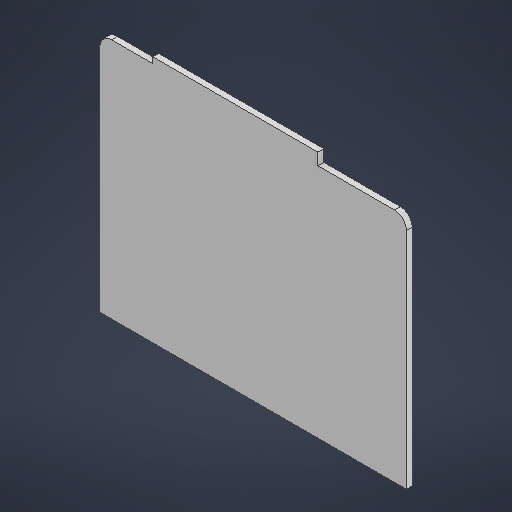
# Autodesk Inventor part: 屏幕pcb
Saved by Autodesk Inventor 2025 (Build 290162000, 162)
## iProperties
Created: 2025-09-15
Part Number: 屏幕pcb
Material: 常规
Document SubType Name: Modeling
Designer: XH
Density: 1 g/cm^3
Appearance: 默认
Author: XH
Autodesk Inventor part; units mm, degrees
ref_plane "YZ Plane" through (0, 0, 0) normal (1, 0, 0) x (0, 1, 0)
ref_plane "XZ Plane" through (0, 0, 0) normal (0, 1, 0) x (-1, 0, 0)
ref_plane "XY Plane" through (0, 0, 0) normal (0, 0, 1) x (1, 0, 0)
sketch "草图1" plane through (0, 0, 0) normal (0, 0, 1) x (1, 0, 0)
  line L0 (26, -21) -> (-26, -21)
  line L1 (-26, -21) -> (-26, 21)
  line L2 (-26, 21) -> (26, 21)
  line L3 (26, 21) -> (26, -21)
  line L4 (26, -21) -> (-26, 21) construction
  line L5 (-26, -21) -> (26, 21) construction
  line L6 (11, 21) -> (26, 21)
  line L7 (26, 21) -> (26, 19)
  line L8 (26, 19) -> (11, 19)
  line L9 (11, 19) -> (11, 21)
  line L10 (-26, 21) -> (-17, 21)
  line L11 (-17, 21) -> (-17, 20)
  line L12 (-17, 20) -> (-26, 20)
  line L13 (-26, 20) -> (-26, 21)
  point P0 (0, 0)
  point P1 (-26, 20.5)
  dimension "d0" = 42
  dimension "d1" = 52
  dimension "d2" = 15
  dimension "d3" = 40
  dimension "d4" = 9
  dimension "d5" = 1
  constraints: 28 end point, 6 parallel, 3 horizontal, 3 midpoint, 3 perpendicular, 2 point on line
  measures "d0" distance of L2.end L0.start
  measures "d1" distance of L1.end L2.end
  measures "d2" distance between parallel lines of L3 L9
  measures "d3" distance between parallel lines of L0 L8
  measures "d4" distance from line of point (-26, 20.5) L11
  measures "d5" distance between parallel lines of L2 L12
extrude "拉伸1" add sketch "草图1" along normal blind 1 contours L0 L1 L12 L11 L2 L9 L8 L3
fillet "圆角1" radius 2 1 edges at (26, 19, 0.5)
fillet "圆角2" radius 2 1 edges at (-26, 20, 0.5)
